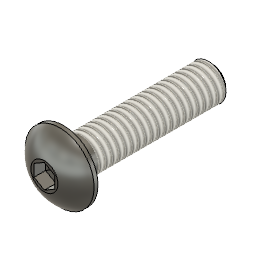
URSA_CNCmill_Aluminium_Bottom (Autodesk Fusion 360 archive; units mm, degrees)
design "Hexagon Socket Button Head Cap Screw ANSI B18.3 - #6-40 x 9/16 Steel Grade 2 Plain"
description: Hexagon Socket Button Head Cap Screw ANSI B18.3 - #6-40 x 9/16
part number: HSBHCS ANSI B18.3 - #6-40 x 9/16 Steel Grade 2 Plain
Autodesk Fusion 360 part; units mm, degrees
sketch "Sketch1" plane through (0, 0, 0) normal (0, 1, 0) x (1, 0, 0)
  line L0 (-1.7526, 0) -> (-1.7526, 14.2875)
  line L1 (-1.7526, 14.2875) -> (0, 14.2875)
  line L2 (0, 14.2875) -> (0, -1.8542)
  line L3 (-1.7526, 0) -> (-3.3274, 0)
  line L4 (0, -1.8542) -> (-1.3043, -1.8542)
  line L5 (-3.3274, 0) -> (-3.3274, -0.381)
  arc A0 (-3.3274, -0.381) -> (-1.3043, -1.8542) centre (0, 2.0627) ccw
  dimension "d9" = 3.5052
  dimension "d66" = 6.6548
  dimension "d129" = 2.6086
  dimension "d130" = 14.2875
  dimension "d131" = 1.8542
  dimension "d132" = 0.381
  constraint perpendicular L0 L1
  constraint perpendicular L0 L3
  constraint coincident origin L3
  constraint vertical L0
  constraint vertical L2
  constraint perpendicular L2 L4
  constraint coincident origin L2
  constraint perpendicular L3 L5
  constraint coincident L2 A0.centre
  measures "d130" distance of origin L1
  measures "d131" distance of L3 L4.end
  measures "d132" distance of L3 L5.end
revolve "Revolve1" add sketch "Sketch1" angle 360 about axis through (0, 0, -14.2875) along (0, 0, 1)
ref_plane "WorkPlane1" through (0, 0, 1.8542) normal (0, 0, 1) x (1, 0, 0)
sketch "Sketch6" plane through (0, 0, 1.8542) normal (0, 0, 1) x (1, 0, 0)
  line L0 (0, -1.1585) -> (1.0033, -0.5793)
  line L1 (1.0033, -0.5793) -> (1.0033, 0.5793)
  line L2 (1.0033, 0.5793) -> (0, 1.1585)
  line L3 (0, 1.1585) -> (-1.0033, 0.5793)
  line L4 (-1.0033, 0.5793) -> (-1.0033, -0.5793)
  line L5 (-1.0033, -0.5793) -> (0, -1.1585)
  dimension "d143" = 2.0066
  constraint vertical L1
  measures "d143" distance of L1 L4
extrude "Extrude1" cut sketch "Sketch6" against normal blind 1.1176
extrude "Extrude2" cut 1 faces at (0, -0.3862, 0.7366) along direction (0, 0, -1) blind 1.1176 draft -85
fillet "Fillet5" radius 0.1753 1 edges at (-1.634, 0.6338, 0)
thread "Thread5" "ANSI Unified Screw Threads 0.138(#6) 6-40 UNF 6-40 UNF 2A" major diameter 3.4214 minor diameter 2.728 pitch 0.635 angle 60 resizes the face on face at (-1.7504, 0.0874, -4.8793) from (0, 0, -1.5902) to (0, 0, -14.2875)
sketch "Sketch7" plane through (0, 0, 0) normal (0, 1, 0) x (1, 0, 0)
  line L0 (-1.7877, 14.2875) -> (-1.7877, 13.909)
  line L1 (-1.7877, 13.909) -> (-1.3741, 14.2875)
  line L2 (0, 14.2875) -> (0, -1.8542)
  line L3 (-1.7877, 14.2875) -> (0, 14.2875)
  dimension "d134" = 0.3785
  dimension "d135" = 1.3741
  dimension "d136" = 1.7877
  constraint coincident L2.start L3.end
  constraint perpendicular L2 L3
  constraint coincident L1.end L3
  constraint perpendicular L0 L3
  measures "d134" distance of L0.end L3
  measures "d135" distance of L1.end L2
  measures "d136" distance of L0.start L2
revolve "Revolve3" cut sketch "Sketch7" angle 360 about axis through (0, 0, 1.75) along (0, 0, 1)
equation "d9 = adsk_nomdia"
equation "d31 = -adsk_phildepth"
equation "d66 = adsk_headdia"
equation "d71 = adsk_headh"
equation "d76 = -adsk_phildepth"
equation "adsk_nomlen = 0.5625 in"
equation "adsk_headh = 0.073 in"
equation "adsk_headdia = 0.262 in"
equation "adsk_nomdia = 0.138 in"
equation "adsk_philwidth = 0.079 in"
equation "adsk_phildepth = 0.044 in"
equation "adsk_thrlen = 0.4998921 in"
equation "adsk_endpointdia = 0.1082 in"
equation "adsk_startlen = 0.0149 in"
equation "adsk_midfillet = adsk_nomdia * 0.05"
equation "d114 = adsk_midfillet"
equation "adsk_baseh = 0.015 in"
equation "d129 = adsk_philwidth * 1.3"
equation "d130 = adsk_nomlen"
equation "d131 = adsk_headh"
equation "d132 = adsk_baseh"
equation "d134 = adsk_startlen"
equation "d135 = adsk_endpointdia / 2"
equation "d136 = adsk_nomdia * 0.51"
equation "d142 = min(adsk_thrlen; adsk_nomlen - adsk_midfillet - 0.001 mm)"
equation "d143 = adsk_philwidth"
